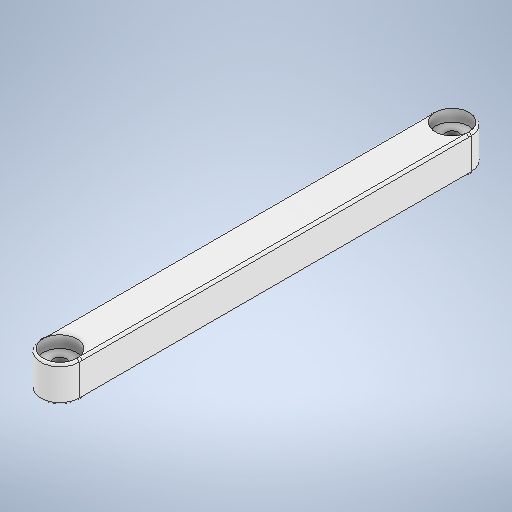
# Autodesk Inventor part: Плечо_переднее
Saved by Autodesk Inventor 2025.1 (Build 291241000, 241)
## iProperties
Created: 2026-10-14
Part Number: Плечо_переднее
Material: Пластик АБС
Document SubType Name: Modeling
Designer: Ваня
Density: 1.06 g/cm^3
Appearance: Гладкий — белый
Author: Ваня
Autodesk Inventor part; units mm, degrees
ref_plane "YZ Plane" through (0, 0, 0) normal (1, 0, 0) x (0, 1, 0)
ref_plane "XZ Plane" through (0, 0, 0) normal (0, 1, 0) x (-1, 0, 0)
sketch "Эскиз1" plane through (0, 0, 0) normal (0, 1, 0) x (-1, 0, 0)
  line L0 (0, 0) -> (16, 0)
  line L1 (16, 0) -> (16, -150)
  line L2 (16, -150) -> (0, -150)
  line L3 (0, -150) -> (0, 0)
  dimension "d0" = 16
  dimension "d1" = 150
  constraints: 8 end point, 2 parallel, 1 horizontal, 1 perpendicular
  measures "d0" distance of L1.end L2.end
  measures "d1" distance of L0.end L1.end
extrude "Выдавливание1" add sketch "Эскиз1" along normal blind 15
sketch "Эскиз2" plane through (0, 0, 0) normal (0, -1, 0) x (1, 0, 0)
  line L0 (-16, 0) -> (0, 0) projected
  line L1 (-8, 0) -> (-8, 7.1)
  circle A0 centre (-8, 7.1) radius 7.1
  circle A1 centre (-8, 7.1) radius 8
  line L2 (0, 7.1) -> (0, 0)
  line L3 (-16, 7.1) -> (-16, 0)
  line L4 (-16, -150) -> (-16, 0) projected
  line L5 (-16, 0) -> (-16, -75)
  line L6 (-16, -75) -> (-21, -75)
  line L7 (-16, -150) -> (0, -150)
  circle A2 centre (-8, -157.1) radius 7.1
  circle A3 centre (-8, -157.1) radius 8
  line L8 (0, -157.1) -> (0, -150)
  line L9 (-16, -157.1) -> (-16, -150)
  point P0 (-8, -150)
  dimension "d4" = 7.1
  dimension "d5" = 75
  dimension "d6" = 5
  constraints: 16 end point, 5 symmetric about line, 4 point on circle, 3 centre point, 3 coincident, 2 midpoint, 2 vertical, 1 parallel, 1 perpendicular, 1 tangent, 1 vertical alignment, 4 other
  measures "d4" distance of L1.start L1.end
  measures "d5" distance of L0.start L5.end
  measures "d6" distance of L5.end L6.end
extrude "Выдавливание2" add sketch "Эскиз2" against normal blind 15 contours L3 A1 L0 | A1 L0 | A1 L2 L0 | L7 A3 L9 | L7 A3 | L7 L8 A3 picked at (-0.3775, 7.7382) picked at (-0.3775, -157.7382)
ref_plane "РабПлоскость1" through (0, 7.5, 0) normal (0, 1, 0) x (1, 0, 0)
sketch "Эскиз3" plane through (0, 7.5, 0) normal (0, 1, 0) x (1, 0, 0)
  circle A0 centre (-8, -7.1) radius 7.1 projected
  circle A1 centre (-8, -7.1) radius 7.1
  circle A2 centre (-8, -7.1) radius 2.65
  line L0 (0, 157.1) -> (0, -7.1) projected
  line L1 (0, 75) -> (5, 75)
  circle A3 centre (-8, 157.1) radius 7.1
  circle A4 centre (-8, 157.1) radius 2.65
  point P0 (0, 0)
  dimension "d10" = 5.3
  dimension "d11" = 5
  constraints: 4 centre point, 2 coincident, 2 end point, 2 symmetric about line, 1 horizontal, 1 midpoint, 2 other
  measures "d10" diameter of A2
  measures "d11" distance of L1.start L1.end
extrude "Выдавливание3" add sketch "Эскиз3" along normal mid plane 2
fillet "Сопряжение1" radius 1 8 edges at (-8, 15, -165.1) (-16, 15, -75) (-8, 15, 15.1) (0, 15, -75) (-8, 0, 15.1) (-16, 0, -75) (-8, 0, -165.1) (0, 0, -75)
move faces "Перенос1" translate (0, 1.5, 0) faces at (-2.4778, 8.5, 7.8778) (-2.4778, 8.5, -156.3222)
